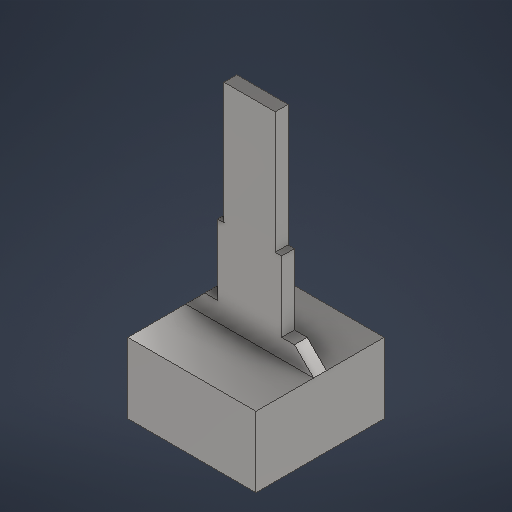
# Autodesk Inventor part: Potikan liuku
Saved by Autodesk Inventor 2026.1 (Build 301233020, 233B)
## iProperties
Created: 2025-11-03
Part Number: Potikan liuku
Material: Steel, Cast
Document SubType Name: Modeling
Designer: kuuse
Density: 7.85 g/cm^3
Appearance: Semi-Polished
Author: kuuse
Autodesk Inventor part; units mm, degrees
ref_plane "YZ Plane" through (0, 0, 0) normal (1, 0, 0) x (0, 1, 0)
ref_plane "XZ Plane" through (0, 0, 0) normal (0, 1, 0) x (-1, 0, 0)
ref_plane "XY Plane" through (0, 0, 0) normal (0, 0, 1) x (1, 0, 0)
sketch "Sketch1" plane through (0, 0, 0) normal (0, 0, 1) x (1, 0, 0)
  line L0 (-2, 0) -> (2, 0)
  line L1 (2, 0) -> (2, -9.5)
  line L2 (2, -9.5) -> (2.5, -9.5)
  line L3 (2.5, -9.5) -> (2.5, -15)
  line L4 (2.5, -15) -> (5, -15)
  line L5 (5, -15) -> (5, -22)
  line L6 (5, -22) -> (-5, -22)
  line L7 (-5, -22) -> (-5, -15)
  line L8 (-2, 0) -> (-2, -9.5)
  line L9 (-2, -9.5) -> (-2.5, -9.5)
  line L10 (-2.5, -9.5) -> (-2.5, -15)
  line L11 (2.5, -15) -> (-2.5, -15)
  line L12 (-2.5, -15) -> (-5, -15)
  line L13 (-5, -16.5) -> (5, -16.5)
  point P0 (0, 0)
  point P1 (0, 0)
  dimension "d0" = 4
  dimension "d1" = 5
  dimension "d2" = 5.5
  dimension "d3" = 15
  dimension "d4" = 7
  dimension "d5" = 10
  dimension "d10" = 1.5
  constraints: 28 end point, 8 perpendicular, 5 point on line, 3 collinear, 2 horizontal, 1 coincident, 1 midpoint
  measures "d0" distance between parallel lines of L8 L1
  measures "d1" distance between parallel lines of L3 L10
  measures "d2" distance of L2.end L3.end
  measures "d3" distance between parallel lines of L4 L0
  measures "d4" distance between parallel lines of L4 L6
  measures "d5" distance between parallel lines of L7 L5
  measures "d10" distance between parallel lines of L12 L13
extrude "Extrusion1" add sketch "Sketch1" along normal mid plane 1 contours L0 L1 L2 L3 L11 L10 L9 L8 | L11 L4 L5 L13 L7 L12
extrude "Extrusion2" add sketch "Sketch1" along normal mid plane 10 contours L13 L5 L6 L7
chamfer "Chamfer1" distance 1.5 angle 45 2 edges at (5, -15, 0) (-5, -15, 0)
body "Solid1"
